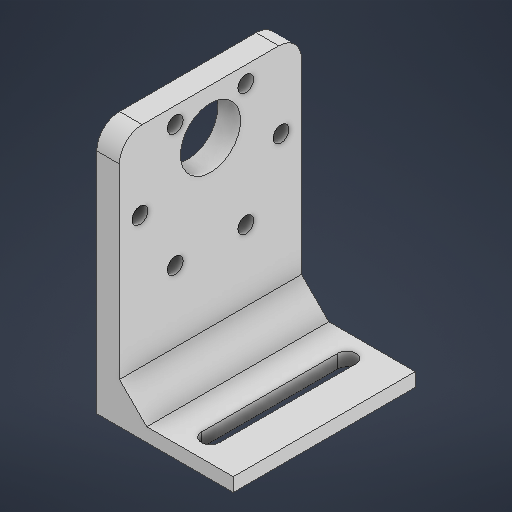
# Autodesk Inventor part: supports_moteurs_petit_robot_v1
Saved by Autodesk Inventor 2026 (Build 300175000, 175)
## iProperties
Created: 2025-05-02
Part Number: supports_moteurs_petit_robot_v1
Material: Générique
Document SubType Name: Modeling
Designer: virgi
Density: 1 g/cm^3
Appearance: Par défaut
Author: virgi
Autodesk Inventor part; units mm, degrees
ref_plane "YZ Plane" through (0, 0, 0) normal (1, 0, 0) x (0, 1, 0)
ref_plane "XZ Plane" through (0, 0, 0) normal (0, 1, 0) x (-1, 0, 0)
ref_plane "XY Plane" through (0, 0, 0) normal (0, 0, 1) x (1, 0, 0)
sketch "Esquisse1" plane through (0, 0, 0) normal (0, 1, 0) x (-1, 0, 0)
  line L0 (-15, -20) -> (15, -20)
  line L1 (15, -20) -> (15, 20)
  line L2 (15, 20) -> (-15, 20)
  line L3 (-15, 20) -> (-15, -20)
  line L4 (-15, -20) -> (15, 20) construction
  line L5 (15, -20) -> (-15, 20) construction
  point P0 (0, 0)
  dimension "d0" = 40
  dimension "d1" = 30
  constraints: 12 end point, 2 midpoint, 2 parallel, 1 horizontal, 1 perpendicular
  measures "d0" distance of L0.end L1.end
  measures "d1" distance of L1.end L2.end
extrude "Extrusion1" add sketch "Esquisse1" along normal blind 3
sketch "Esquisse2" plane through (0, 3, 0) normal (0, 1, 0) x (1, 0, 0)
  line L0 (-15, 20) -> (-15, -20) projected
  line L1 (-10, 20) -> (-15, 20)
  line L2 (-15, 20) -> (-15, -20)
  line L3 (-15, -20) -> (-10, -20)
  line L4 (-10, -20) -> (-10, 20)
  line L5 (-10, 20) -> (-15, -20) construction
  line L6 (-15, 20) -> (-10, -20) construction
  point P0 (0, 0)
  point P1 (-12.5, 0)
  point P2 (-10, 18.6397)
  dimension "d4" = 5
  constraints: 12 end point, 3 parallel, 2 midpoint, 1 horizontal, 1 perpendicular, 1 point on line
  measures "d4" distance of L0.end L3.end
extrude "Extrusion2" add sketch "Esquisse2" along normal blind 52
sketch "Esquisse3" plane through (-10, 3, 20) normal (1, 0, 0) x (0, 0, -1)
  line L0 (0, 0) -> (0, 52) projected
  line L1 (40, 0) -> (0, 0) projected
  line L2 (40, -3) -> (0, -3) projected
  point P0 (20, -3)
  point P1 (20, 42)
  dimension "d14" = 20
  dimension "d70" = 45
  measures "d14" distance from line of L0 point (20, 42)
  measures "d70" distance from line of L2 point (20, 42)
hole "Perçage1" at (-10, 45, 0) direction (-1, 0, 0) diameter 13.2 end through all
sketch "Esquisse9" plane through (0, 0, 0) normal (0, -1, 0) x (1, 0, 0)
  line L0 (5, 15) -> (5, -15) construction
  line L1 (7, 15) -> (7, -15)
  line L2 (3, -15) -> (3, 15)
  arc A0 (7, 15) -> (3, 15) centre (5, 15) ccw
  arc A1 (3, -15) -> (7, -15) centre (5, -15) ccw
  line L3 (-15, -6.6) -> (-15, 6.6) projected
  line L4 (-15, 20) -> (15, 20) projected
  point P0 (0, 0)
  point P1 (5, 0)
  dimension "d42" = 20
  dimension "d43" = 4
  dimension "d44" = 30
  dimension "d45" = 5
  constraints: 8 end point, 4 point on circle, 4 tangent, 2 centre point, 1 midpoint, 1 parallel, 1 vertical
  measures "d42" distance between parallel lines of L3 L0
  measures "d43" distance between parallel lines of L2 L1
  measures "d44" distance of L0.end L0.start
  measures "d45" distance from line of L4 L0.start
extrude "Extrusion3" cut sketch "Esquisse9" against normal through all
sketch "Esquisse13" plane through (-15, 0, -20) normal (-1, 0, 0) x (0, 0, 1)
  circle A0 centre (20, 45) radius 6.6 projected
  line L0 (20, -4.9406) -> (20, 55.8807) construction
  line L1 (0, 0) -> (40, 0) construction
  line L2 (33.0241, 38) -> (6.5713, 38) construction
  point P0 (20, 0)
  point P1 (20, 38)
  point P2 (35.5, 38)
  point P3 (20, 38)
  point P4 (27.75, 51.4234)
  point P5 (20, 38)
  point P6 (12.25, 51.4234)
  point P7 (20, 38)
  point P8 (4.5, 38)
  point P9 (20, 38)
  point P10 (12.25, 24.5766)
  point P11 (20, 38)
  point P12 (27.75, 24.5766)
  point P13 (20, 0)
  point P14 (15.6919, 50)
  point P15 (24.3081, 50)
  dimension "d71" = 7
  dimension "d72" = 15.5
  dimension "d75" = 360
  constraints: 4 end point, 4 point on line, 2 coincident, 1 horizontal, 1 midpoint, 1 vertical, 11 other
  measures "d71" distance of point (20, 38) A0.centre
  measures "d72" distance of point (35.5, 38) point (20, 38)
hole "Perçage6" at (-15, 24.5766, 7.75) at (-15, 38, 15.5) at (-15, 51.4234, 7.75) at (-15, 51.4234, -7.75) at (-15, 38, -15.5) at (-15, 24.5766, -7.75) direction (1, 0, 0) diameter 3.5 end through all
fillet "Congé1" radius 5 2 edges at (-12.5, 55, 20) (-12.5, 55, -20)
chamfer "Chanfrein1" distance 6 angle 45 1 edges at (-10, 3, 0)
